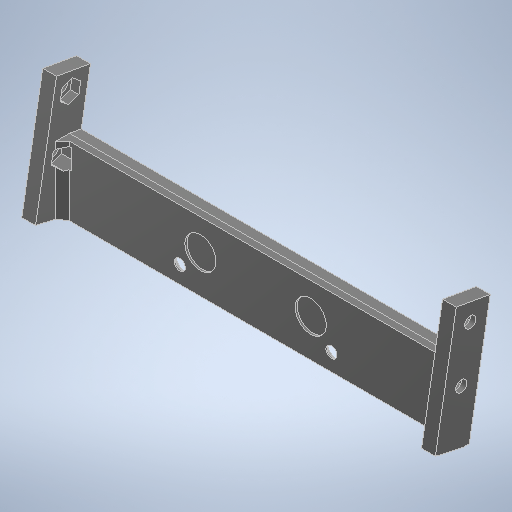
# Autodesk Inventor part: M5_mount
Saved by Autodesk Inventor 2025.3 (Build 293356030, 356C)
## iProperties
Created: 2025-08-01
Part Number: M5_mount
Material: 一般
Document SubType Name: Modeling
Designer: ibuki_ono
Density: 1 g/cm^3
Appearance: 滑らか - 黒
Author: ibuki_ono
## iProperties of the stored document M5_mount_3D プリント.ipt
Created: 2025-08-01
Part Number: M5_mount_3D プリント
Material: 一般
Document SubType Name: Modeling
Designer: ibuki_ono
Density: 1 g/cm^3
Appearance: 既定
Author: ibuki_ono
Autodesk Inventor part; units mm, degrees
ref_plane "YZ Plane" through (0, 0, 0) normal (1, 0, 0) x (0, 1, 0)
ref_plane "XZ Plane" through (0, 0, 0) normal (0, 1, 0) x (-1, 0, 0)
ref_plane "XY Plane" through (0, 0, 0) normal (0, 0, 1) x (1, 0, 0)
sketch "スケッチ1" plane through (0, 0, 0) normal (0, 0, 1) x (1, 0, 0)
  line L0 (-60, -10) -> (60, -10)
  line L1 (60, -10) -> (60, 10)
  line L2 (60, 10) -> (-60, 10)
  line L3 (-60, 10) -> (-60, -10)
  line L4 (-60, -10) -> (60, 10) construction
  line L5 (60, -10) -> (-60, 10) construction
  point P0 (0, 0)
  dimension "d0" = 120
  dimension "d1" = 20
  constraints: 12 end point, 2 midpoint, 2 parallel, 1 horizontal, 1 perpendicular
  measures "d0" distance of L2.end L1.end
  measures "d1" distance of L1.end L0.end
extrude "押し出し1" add sketch "スケッチ1" along normal mid plane 2
sketch "スケッチ2" plane through (0, 0, -1) normal (0, 0, -1) x (-1, 0, 0)
  line L0 (-60, -10) -> (60, -10) projected
  line L1 (-22, -5) -> (22, -5) construction
  point P0 (0, 0)
  point P1 (0, -5)
  point P2 (0, -10)
  dimension "d4" = 44
  dimension "d5" = 5
  constraints: 2 coincident, 2 end point, 2 midpoint, 1 horizontal, 1 vertical alignment
  measures "d4" distance of L1.start L1.end
  measures "d5" distance between parallel lines of L0 L1
hole "穴1" at (22, -5, -1) at (-22, -5, -1) direction (0, 0, 1) diameter 3.2 end through all
sketch "スケッチ3" plane through (60, -10, 1) normal (1, 0, 0) x (0, 0, -1)
  line L0 (2, 20) -> (2, 0) projected
  line L1 (0, 0) -> (0, 20) projected
  line L2 (0, 0) -> (2, 0) projected
  line L3 (2, 0) -> (-7.8481, 1.7365)
  line L4 (-7.8481, 1.7365) -> (-1.7704, 36.2048)
  line L5 (-1.7704, 36.2048) -> (8.0777, 34.4683)
  line L6 (8.0777, 34.4683) -> (2, 0)
  line L7 (2, 0) -> (12, 0) construction
  line L8 (-7.8481, 1.7365) -> (0, 0)
  point P0 (1, 10)
  dimension "d13" = 10
  dimension "d14" = 170
  dimension "d15" = 35
  constraints: 12 end point, 2 parallel, 1 equal length, 1 horizontal, 1 perpendicular
  measures "d13" distance of L0.end L3.end
  measures "d14" angle of L7 L3
  measures "d15" distance of L3.end L4.end
extrude "押し出し2" add sketch "スケッチ3" against normal blind 4
sketch "スケッチ4" plane through (60, -10, 1) normal (1, 0, 0) x (0, 0, -1)
  line L0 (8.0777, 34.4683) -> (-1.7704, 36.2048) projected
  line L1 (3.1536, 35.3365) -> (-0.3193, 15.6404) construction
  point P0 (1, 10)
  point P1 (2.2854, 30.4125)
  dimension "d18" = 20
  dimension "d19" = 5
  constraints: 2 end point, 1 coincident, 1 midpoint, 1 perpendicular, 1 point on line
  measures "d18" distance of L1.start L1.end
  measures "d19" distance from line of L0 point (2.285, 30.412)
hole "穴2" at (60, 5.6404, 1.3193) at (60, 20.4125, -1.2854) direction (-1, 0, 0) diameter 3.2 depth 4
sketch "スケッチ5" plane through (56, -10, 1) normal (-1, 0, 0) x (0, 0, 1)
  arc A0 (0, 14.0725) -> (0, 17.2082) centre (0.3193, 15.6404) ccw projected
  circle A1 centre (-2.2854, 30.4125) radius 1.6 projected
  line L0 (-2.8368, 33.5397) -> (0.1471, 32.4536)
  line L1 (0.1471, 32.4536) -> (0.6985, 29.3264)
  line L2 (0.6985, 29.3264) -> (-1.734, 27.2853)
  line L3 (-1.734, 27.2853) -> (-4.7179, 28.3713)
  line L4 (-4.7179, 28.3713) -> (-5.2693, 31.4985)
  line L5 (-5.2693, 31.4985) -> (-2.8368, 33.5397)
  line L6 (0.8707, 12.5132) -> (-2.1132, 13.5992)
  line L7 (-2.1132, 13.5992) -> (-2.6646, 16.7264)
  line L8 (-2.6646, 16.7264) -> (-0.2321, 18.7675)
  line L9 (-0.2321, 18.7675) -> (2.7518, 17.6815)
  line L10 (2.7518, 17.6815) -> (3.3032, 14.5543)
  line L11 (3.3032, 14.5543) -> (0.8707, 12.5132)
  line L12 (1.7704, 36.2048) -> (-8.0777, 34.4683) projected
  line L13 (-3.1536, 35.3365) -> (1.1876, 10.7163) construction
  point P0 (-1, 10)
  dimension "d27" = 25
  dimension "d28" = 5.5
  dimension "d29" = 5.5
  constraints: 26 end point, 2 coincident, 2 point on line, 1 midpoint, 1 perpendicular, 26 other
  measures "d27" distance of L13.start L13.end
  measures "d28" distance between parallel lines of L4 L1
  measures "d29" distance between parallel lines of L7 L10
extrude "押し出し3" cut sketch "スケッチ5" along normal mid plane 5 contours A1 | L0 L1 L2 L3 L4 L5 | L6 L7 L8 L9 L10 L11
sketch "スケッチ6" plane through (56, -10, 1) normal (-1, 0, 0) x (0, 0, 1)
  line L0 (-2.1132, 13.5992) -> (-2.6646, 16.7264) projected
  line L1 (-2.6646, 16.7264) -> (-2, 17.2841) projected
  line L2 (0, 20) -> (-2, 20) projected
  line L3 (-8.0777, 34.4683) -> (-2, 0) projected
  line L4 (-2, 20) -> (-5.4202, 19.3969)
  line L5 (-2, 20) -> (-2, 0) projected
  line L6 (-2, 8.1234) -> (-3.3892, 7.8785)
  line L7 (-2, 0) -> (-2, 20) projected
  circle A0 centre (0.3193, 15.6404) radius 1.6 projected
  line L8 (2.7518, 17.6815) -> (3.3032, 14.5543) projected
  line L9 (-0.2321, 18.7675) -> (2.7518, 17.6815) projected
  line L10 (-2.6646, 16.7264) -> (-0.2321, 18.7675) projected
  line L11 (-2.1132, 13.5992) -> (-2.6646, 16.7264) projected
  line L12 (0.8707, 12.5132) -> (-2.1132, 13.5992) projected
  line L13 (3.3032, 14.5543) -> (0.8707, 12.5132) projected
  point P0 (-1, 10)
  point P1 (-2, 10.5814)
  point P2 (-2, 17.2841)
  point P3 (0, 13.375)
  point P4 (0.6261, 13.9004)
  point P5 (-2, 13.558)
  point P6 (-2, 17.2841)
  dimension "d32" = 8
  constraints: 4 end point, 3 point on line, 2 perpendicular, 2 other
  measures "d32" distance from line of L3.end L6
extrude "押し出し4" add sketch "スケッチ6" along normal blind 2.5 contours L12 L5 L6 L3 L4 L1 L0
sketch "スケッチ7" plane through (53.5, -10, 1) normal (-1, 0, 0) x (0, 0, 1)
  line L0 (-2, 0) -> (-2, 20) projected
  line L1 (-2, 20) -> (-5.4202, 19.3969) projected
  line L2 (-5.4202, 19.3969) -> (-3.3892, 7.8785) projected
  line L3 (-2, 13.558) -> (-2, 8.1234) projected
  line L4 (-3.3892, 7.8785) -> (-2, 8.1234) projected
  line L5 (-2, 20) -> (-2, 17.2841) projected
  line L6 (-2.1132, 13.5992) -> (-2.6646, 16.7264) projected
  line L7 (-2.6646, 16.7264) -> (-2, 17.2841) projected
  line L8 (-2, 13.558) -> (-2.1132, 13.5992) projected
  point P0 (-1, 10)
extrude "押し出し5" add sketch "スケッチ7" along normal up to surface (53.5 mm away) contours L4 L2 L1 L0 L7 L6 L8
mirror "ミラー1" about plane through (0, 0, 0) normal (1, 0, 0) of "押し出し2", "穴2", "押し出し3", "押し出し4", "押し出し5"
chamfer "面取り1" distance 1.6 angle 45 2 edges at (22, -6.6, -1) (-22, -6.6, -1)
chamfer "面取り2" distance 2 angle 45 4 edges at (-56, -3.585, 1) (-56, 9.3415, 1) (56, 9.3415, 1) (56, -3.585, 1)
sketch "スケッチ8" plane through (0, 0, 1) normal (0, 0, 1) x (1, 0, 0)
  line L0 (54, 10) -> (-54, 10) projected
  circle A0 centre (-16, 1) radius 4.5
  circle A1 centre (16, 1) radius 4.5
  circle A2 centre (-22, -5) radius 1.6 projected
  circle A3 centre (22, -5) radius 1.6 projected
  point P0 (0, 0)
  dimension "d43" = 9
  dimension "d44" = 9
  dimension "d45" = 6
  dimension "d46" = 6
  dimension "d47" = 6
  dimension "d48" = 6
  constraints: 2 centre point
  measures "d43" diameter of A0
  measures "d44" diameter of A1
  measures "d45" horizontal distance of A2.centre A0.centre
  measures "d46" horizontal distance of A3.centre A1.centre
  measures "d47" horizontal distance of A0.centre A2.centre
  measures "d48" horizontal distance of A1.centre A3.centre
extrude "押し出し6" cut sketch "スケッチ8" against normal blind 0.6 contours A0 | A1
equation "\"d29\" = d28"
equation "\"d43\" = d44"
equation "\"d46\" = d45"
equation "\"d47\" = d45"
equation "\"d48\" = d45"
